211303_P01_WALL-SKIN-SIDE-UPPER-LH_CAD (Autodesk Fusion 360 design; units mm, degrees)
part number: 2026-11-01-23-47-04-714
description: WALL - SKIN - SIDE UPPER - LH | Vách trái - tấm ốp alu trên | P01
part number: 211303
Autodesk Fusion 360 part; units mm, degrees
ref_plane "WorkPlane1" through (0, 0, 1257.26) normal (0, 0, 1) x (1, 0, 0) in component "211303 WALL - SKIN - SIDE UPPER - LH"
sketch "SKETCH - SKIN PLATE" plane through (0, 0, 1257.26) normal (0, 0, 1) x (1, 0, 0) in component "211303 WALL - SKIN - SIDE UPPER - LH"
  line L0 (-1250, -642.74) -> (-1247, -642.74)
  line L1 (-1247, -642.74) -> (-1247, 850)
  line L2 (-1247, 850) -> (-1250, 850)
  line L3 (-1250, 850) -> (-1250, -642.74)
  dimension "d176" = 3
  dimension "d177" = 1492.74
  dimension "d178" = 1250
  dimension "d179" = 642.74
  constraint horizontal L0
  constraint vertical L1
  constraint horizontal L2
  constraint vertical L3
  measures "d176" horizontal distance of L0.start L0.end
  measures "d177" vertical distance of L0.start L2.end
  measures "d178" horizontal distance of origin L0.start
  measures "d179" vertical distance of origin L0.start
extrude "EXTRUDE - SKIN PLATE" add sketch "SKETCH - SKIN PLATE" along normal blind 1142.74 in component "211303 WALL - SKIN - SIDE UPPER - LH"
ref_plane "WorkPlane2" through (0, 0, 1257.26) normal (0, 0, 1) x (1, 0, 0) in component "211303 WALL - SKIN - SIDE UPPER - LH"
sketch "SKETCH - SKIN BACK RETURN" plane through (0, 0, 1257.26) normal (0, 0, 1) x (1, 0, 0) in component "211303 WALL - SKIN - SIDE UPPER - LH"
  line L0 (-1247, 847) -> (-1204, 847)
  line L1 (-1204, 847) -> (-1204, 850)
  line L2 (-1204, 850) -> (-1247, 850)
  line L3 (-1247, 850) -> (-1247, 847)
  dimension "d184" = 43
  dimension "d185" = 3
  dimension "d186" = 1247
  dimension "d187" = 847
  constraint horizontal L0
  constraint vertical L1
  constraint horizontal L2
  constraint vertical L3
  measures "d184" horizontal distance of L0.start L0.end
  measures "d185" vertical distance of L0.start L2.end
  measures "d186" horizontal distance of origin L0.start
  measures "d187" vertical distance of origin L0.start
extrude "JOIN - SKIN BACK RETURN" add sketch "SKETCH - SKIN BACK RETURN" along normal blind 1142.74 in component "211303 WALL - SKIN - SIDE UPPER - LH"
fillet "FILLET - FOLD OUTSIDE RADIUS (MAKER'S GUIDE 4.5)" radius 2 1 edges at (-1250, 850, 1828.63) in component "211303 WALL - SKIN - SIDE UPPER - LH"
component "211303 WALL - SKIN - SIDE UPPER - LH" placed x (1, 0, 0) y (0, 1, 0) z (0, 0, 1) at (0, 0, 0)
equation "pod_w_Ref = 2500 mm" comment "DECIDED: D-01; conventions s4 (X = +-1250)"
equation "pod_d_Ref = 1700 mm" comment "DECIDED: D-01; conventions s4 (Y = +-850)"
equation "pod_h_Ref = 2400 mm" comment "DECIDED: D-21 (room floor to roof skin top)"
equation "glide_h_Ref = 10 mm" comment "ASSUMPTION: layout study inputs.py glide_h"
equation "band_h_Ref = 100 mm" comment "SOURCE: layout study B1 list B-BAND 100x40; inputs.py base_h"
equation "outer_t_Ref = skin_t_Ref + bond_t_Ref + frame_t_Ref" comment "DECIDED: PM ruling 2026-10-31: ACP 3 + bond line 3 + frame 40, walls and ceiling (was 43)"
equation "cav_gap_Ref = 4 mm" comment "DECIDED: D-16, D-42: the gap between the outer panel and the lining cassette in the wall and ceiling stack"
equation "cass_t_Ref = 34 mm" comment "SOURCE: layout study B1 final list L-CASS 34 (tray + 25 gap + felt 9)"
equation "stack_t_Ref = outer_t_Ref + cav_gap_Ref + cass_t_Ref" comment "CALCULATION: D-16, D-42 stack, walls and ceiling: outer panel + cavity gap + cassette (PM ruling 2026-10-31 on outer_t)"
equation "wall_depth_Ref = 1495 mm" comment "DECIDED: PM ruling pass C: side walls start at the decor back plate (Y -645), as v1 (1496)"
equation "lin_gap_Ref = 4 mm" comment "ASSUMPTION: PM ruling pass C: gap above the upper side linings so they stay floating (= the 4 mm stack gap)"
equation "seam_gap_Ref = 2.26 mm" comment "DECIDED: PM ruling 2026-10-31 (Mechanical Checker F-001, F-005): the Joints Engineer's 2.26 mm at all nine site seam types, set by a metal stop (1.5 stop washer + 0.76 rivnut head; joints register section 2.8)"
equation "wall_z0_Ref = glide_h_Ref + band_h_Ref" comment "CALCULATION: base band top: glides + band"
equation "panel_z0_Ref = wall_z0_Ref + seam_gap_Ref" comment "CALCULATION: walls stand one seam_gap above the band top (joints register 2.8, IF-01)"
equation "wall_h_Ref = pod_h_Ref - wall_z0_Ref" comment "CALCULATION: 2290 = layout study v2_model wall_h"
equation "side_h_Ref = ( wall_h_Ref - 2 * seam_gap_Ref ) / 2" comment "CALCULATION: D-23: 2 sheets per side wall; the gap on the band and the horizontal seam (joints register 2.8)"
equation "back_oh_Ref = pod_h_Ref - outer_t_Ref - seam_gap_Ref - panel_z0_Ref" comment "CALCULATION: PM ruling 2026-10-31 (pass D, F-004): the back outer frames run up to the ceiling frame (pod_h - outer_t), less the seam_gap under it, closing the slot at the back top edge"
equation "back_ph_Ref = ( back_oh_Ref - seam_gap_Ref ) / 2" comment "CALCULATION: D-23: 4 sheets on the back, two equal rows with one seam_gap between them (joints register 2.8); the lower back linings match the lower row, as on the side walls"
equation "n_base_bolt_Ref = 4" comment "DECIDED: PM ruling 2026-10-31, J-BASE-01: bolts per panel along the band, evenly spaced"
equation "skin_t_Ref = 3 mm" comment "DECIDED: ACP skin, walls and ceiling (D-16; PM ruling 2026-10-31 on outer_t)"
equation "bond_t_Ref = 3 mm" comment "DECIDED: bond line between the ACP and the frame (PM ruling 2026-10-31 on outer_t)"
equation "frame_t_Ref = 40 mm" comment "DECIDED: aluminium frame tube depth, walls and ceiling (PM ruling 2026-10-31 on outer_t)"
equation "bolt_edge_inset_Ref = 220 mm" comment "DECIDED: PM ruling 2026-10-31: on every bolted edge the end bolts sit this far in from each panel end (the FRAME end, where the bolts go), the rest evenly spaced"
equation "spigot_inset_Ref = 100 mm" comment "DECIDED: PM ruling 2026-10-31: locating spigots this far in from each panel end (round hole at one end, slot at the other)"
equation "ceil_bolt_z_Ref = pod_h_Ref - outer_t_Ref + frame_t_Ref / 2" comment "DECIDED: PM ruling 2026-10-31, J-CEIL-01 wall to ceiling: the bolt line on the ceiling frame's centre (Z 2374)"
equation "pod_w = pod_w_Ref" comment "LINKED: pod_w_Ref, derived from 100000_P04_POD-SKELETON_CAD v6 (skeleton is the single source)"
equation "pod_d = pod_d_Ref" comment "LINKED: pod_d_Ref, derived from 100000_P04_POD-SKELETON_CAD v6 (skeleton is the single source)"
equation "pod_h = pod_h_Ref" comment "LINKED: pod_h_Ref, derived from 100000_P04_POD-SKELETON_CAD v6 (skeleton is the single source)"
equation "wall_depth = wall_depth_Ref" comment "LINKED: wall_depth_Ref, derived from 100000_P04_POD-SKELETON_CAD v6 (skeleton is the single source)"
equation "wall_z0 = wall_z0_Ref" comment "LINKED: wall_z0_Ref, derived from 100000_P04_POD-SKELETON_CAD v6 (skeleton is the single source)"
equation "panel_z0 = panel_z0_Ref" comment "LINKED: panel_z0_Ref, derived from 100000_P04_POD-SKELETON_CAD v6 (skeleton is the single source)"
equation "side_h = side_h_Ref" comment "LINKED: side_h_Ref, derived from 100000_P04_POD-SKELETON_CAD v6 (skeleton is the single source)"
equation "back_ph = back_ph_Ref" comment "LINKED: back_ph_Ref, derived from 100000_P04_POD-SKELETON_CAD v6 (skeleton is the single source)"
equation "stack_t = stack_t_Ref" comment "LINKED: stack_t_Ref, derived from 100000_P04_POD-SKELETON_CAD v6 (skeleton is the single source)"
equation "outer_t = outer_t_Ref" comment "LINKED: outer_t_Ref, derived from 100000_P04_POD-SKELETON_CAD v6 (skeleton is the single source)"
equation "cass_t = cass_t_Ref" comment "LINKED: cass_t_Ref, derived from 100000_P04_POD-SKELETON_CAD v6 (skeleton is the single source)"
equation "lin_gap = lin_gap_Ref" comment "LINKED: lin_gap_Ref, derived from 100000_P04_POD-SKELETON_CAD v6 (skeleton is the single source)"
equation "seam_gap = seam_gap_Ref" comment "LINKED: seam_gap_Ref, derived from 100000_P04_POD-SKELETON_CAD v6 (skeleton is the single source)"
equation "skin_t = skin_t_Ref" comment "LINKED: skin_t_Ref, derived from 100000_P04_POD-SKELETON_CAD v6 (skeleton is the single source)"
equation "bond_t = bond_t_Ref" comment "LINKED: bond_t_Ref, derived from 100000_P04_POD-SKELETON_CAD v6 (skeleton is the single source)"
equation "bolt_edge_inset = bolt_edge_inset_Ref" comment "LINKED: bolt_edge_inset_Ref, derived from 100000_P04_POD-SKELETON_CAD v6 (skeleton is the single source)"
equation "spigot_inset = spigot_inset_Ref" comment "LINKED: spigot_inset_Ref, derived from 100000_P04_POD-SKELETON_CAD v6 (skeleton is the single source)"
equation "n_base_bolt = n_base_bolt_Ref" comment "LINKED: n_base_bolt_Ref, derived from 100000_P04_POD-SKELETON_CAD v6 (skeleton is the single source)"
equation "ceil_bolt_z = ceil_bolt_z_Ref" comment "LINKED: ceil_bolt_z_Ref, derived from 100000_P04_POD-SKELETON_CAD v6 (skeleton is the single source)"
equation "tube_w = 20 mm" comment "CONFIRMED: D-34, D-54, kept by D-131 (the same outside sections in welded, galvanized steel box tube): 20 x 40; the 20 mm face carries the skin, so the 40 mm runs through the wall (outer_t = ACP 3 + frame 40)"
equation "tube_d = outer_t - skin_t - bond_t" comment "CALCULATION: frame depth = outer panel 46 - skin 3 - bond 3 = 40 (D-34)"
equation "tube_t = 1.2 mm" comment "SOURCE: the Joints Engineer's gauges for D-131 (PM ruling, 2026-11-01 05:29): 1.2 for a side panel's rails and front stile, for margin against thin tube and weak welds (corner lift 74% on L1 and L2)"
equation "corner_t = 1.0 mm" comment "SOURCE: the same: the 40 x 40 members (the back stile, and the upper panel's top member) stay 1.0"
equation "stud_t = 0.8 mm" comment "SOURCE: the same: the studs at 0.8 (no rivnut, only the skin's bond line)"
equation "plate_t = 2 mm" comment "SOURCE: the Joints Engineer's corner detail (2026-11-01 05:05): a 2 mm steel plate welded into each mitre, the members cut back so it fits, centred on the old mitre line"
equation "stile_pitch_max = 300 mm" comment "CONFIRMED: PM ruling 2026-11-01 (D-131 sample): the ACP flexes 2 mm or less under a 100 N push at a bay's centre, edges simply supported (make_acp_spans.py), so members about 300 apart; it was 400 (D-16, D-34)"
equation "pnl_len = wall_depth - seam_gap" comment "CALCULATION: D-49 depth 1495 less the 2.26 gap at the decor back plate (PM ruling on F-008): 1492.74"
equation "pnl_h = pod_h - ( panel_z0 + side_h + seam_gap )" comment "CALCULATION: lower: skeleton side_h (2 sheets per side wall, D-23); upper: from one seam gap above the lower row to the roof datum pod_h, as the skeleton's envelope (equal to side_h at P04 values)"
equation "skin_ret = outer_t - skin_t" comment "ASSUMPTION: back return of the side skin: covers the frame's back end at the corner, where the side skin covers the back panel's edge (D-55; sample drawing D04). V-groove and fold per the ACP maker (HOLD H16)"
equation "skin_fold_r = 2 mm" comment "SOURCE: outside radius of the back return's V-grooved fold: over 2 at the fold (the panel maker's guide 01/2021/HDTC-VD 4.5 and figure 4.5: under 2 cracks the face and voids the warranty); modelled (the Lead's ruling, 2026-11-01)"
equation "skin_setback = 0 mm" comment "ASSUMPTION: skin edge set back from the frame's top and bottom edges: 0, so the outside reveal equals the 2.26 seam gap (D-23: crisp, aligned reveals; joints register 2.8 leaves the setback to the WALL drawing)"
equation "frm_len = pnl_len - skin_t - bond_t" comment "CALCULATION: the frame stops one bond line (bond_t) inside the skin's back return, which is bonded to it as the main face is (the Lead's ruling, 2026-11-01: every skin face that meets a frame is bonded at bond_t, no zero fits)"
equation "frm_h = pnl_h" comment "ASSUMPTION: the frame fills the skeleton envelope height; seam and base gasket gaps are set by the joint register (HOLD)"
equation "corner_w = 40 mm" comment "CONFIRMED: the side panel's back member is 40 x 40 x 1.2 (PM ruling on the joints register, item 3, 2026-10-31; register F2, FR-06): the back corner joint needs a 37+ mm overlap for the rivnut and the bolt"
equation "stile_n_mid = 5" comment "CALCULATION: D-131 sample (PM 2026-11-01): 5 studs, placed clear of the bolts (stud_c1 to stud_c5): 4 even studs about 300 apart pass the skin's 2 mm limit but stand 14 and 24 mm from two bolts, under R-J14's 30"
equation "top_h = corner_w" comment "CONFIRMED: top member height: 20 on a lower panel; 40 x 40 on an upper panel, where the ceiling bolts in (PM ruling R-J3, joints register FR-06)"
equation "stile_len = frm_h - tube_w - top_h" comment "CALCULATION: stiles fit between the full-length rails (butt joints)"
equation "ceil_bolt_dz = pod_h - ceil_bolt_z" comment "CALCULATION: J-CEIL-01 side bolts on the ceiling frame tube's centre: the skeleton's ceil_bolt_z, Z 2374 on P04 (joints register R-J15, FR-07)"
equation "fill_t = tube_d" comment "CALCULATION: 40 mm PET fill fills the frame depth (D-34; layout study 40 mm)"
equation "bolt_d = 7 mm" comment "CONFIRMED: PM ruling on F-009: bolt holes 7.0 (0.51 float), position tolerance 0.4 (+-0.2) from the spigot hole, CNC or drill jig (joints register FR-02)"
equation "access_d = 19 mm" comment "CALCULATION: register FR-03: passes the 18 mm head washer (ISO 7093-1, R-J10), the M6 head and the 5 mm key; holds the grommet retainer (H-02)"
equation "bolt_line_y = pod_d / 2 - skin_t - bond_t - tube_d / 2" comment "CONFIRMED: J-WALL-02 bolt line on the back panel's tube centre, Y 824 (joints register R-J15, FR-07)"
equation "rivnut_d = 10 mm" comment "CONFIRMED: D-163 (the Lead's ruling, 2026-11-01): Sherex CAL2-610-4.2 in a round drilled hole Ø10.00 +0.10/0, inside the maker's 10.00 +0.15/-0.0 (Sherex drawing CAL2-610-4.2 rev B, note 2) so the bolt-hole stack ST-03 stays positive; T06's spin-out test confirms it"
equation "spigot_d = 8.5 mm" comment "ASSUMPTION: register FR-05: hole for the 8 mm locating spigot H-05"
equation "pin_slot_w = 8.5 mm" comment "CONFIRMED: D-169 (Joints, 2026-11-01): the decor block's pin slots 8.5 wide in X"
equation "pin_slot_l = 12 mm" comment "CONFIRMED: D-169: 12 long in Z, along the member; on the bolt line, 100 from each end of the seam edge (the register's spigot rule)"
equation "spigot_slot = 16 mm" comment "CONFIRMED: D-167 (the Lead's ruling, 2026-11-01): the seam gasket is 4.78 (PORON 4701-40's standard), so the side panels' back-end slot for the second spigot grows from 8.5 x 14 to 8.5 x 16, ±4 of travel, the panel held 3.4 out"
equation "spigot_edge = spigot_inset" comment "CALCULATION: the skeleton's spigot_inset: spigots 100 from each end of the edge (PM ruling 2026-10-31, R-J13)"
equation "bolt_edge = bolt_edge_inset" comment "CALCULATION: the skeleton's bolt_edge_inset: end bolts 220 in from the panel's ends, evenly spaced, every bolt 30 or more from any stile (PM ruling 2026-10-31, R-J14)"
equation "n_side_jnt = 3" comment "SOURCE: register J-WALL-02, J-FRONT-01: 3 bolts up each side panel"
equation "side_jnt_pitch = ( pnl_h - 2 * bolt_edge ) / ( n_side_jnt - 1 )" comment "CALCULATION: equal pitch of the 3 bolts up the corner and decor joints"
equation "pocket_w = 60 mm" comment "ASSUMPTION: register FR-10: fill left out 60 x 60 next to each bolt for the key"
equation "corner_z0 = panel_z0 + back_ph + seam_gap" comment "CALCULATION: bottom of the back panel row this side panel meets at the corner (B1/B2 or B3/B4, skeleton P04)"
equation "corner_bolt_pitch = ( back_ph - 2 * bolt_edge ) / ( n_side_jnt - 1 )" comment "CALCULATION: J-WALL-02 bolts run along the back panel's edge: 220, 559.31, 898.61 on its 1118.61 (joints register 2.9)"
equation "n_len_bolt = n_base_bolt" comment "CALCULATION: the skeleton's n_base_bolt (4): the same count on J-WALL-01 and the J-CEIL-01 side edges (register 2.9)"
equation "ceil_bolt_pitch = ( wall_depth - 2 * bolt_edge ) / ( n_len_bolt - 1 )" comment "CALCULATION: J-CEIL-01 side edge: 4 bolts along the ceiling's 1495 from Y -645 (its front edge), 220 rule, pitch 351.67 on P04; CEILING drills the same (PM ruling 2026-10-31 16:55; joints register 2.9)"
equation "len_bolt_pitch = ( pnl_len - 2 * bolt_edge ) / ( n_len_bolt - 1 )" comment "CALCULATION: even pitch of the bolts along the panel"
equation "stud_c1 = bolt_edge + 50 mm" comment "CALCULATION: 50 past the 1st bolt: its face 40 clear of it (R-J14)"
equation "stud_c2 = bolt_edge + len_bolt_pitch - 50 mm" comment "CALCULATION: 50 before the 2nd bolt (R-J14)"
equation "stud_c3 = bolt_edge + 1.5 * len_bolt_pitch" comment "CALCULATION: midway between the 2nd and 3rd bolts"
equation "stud_c4 = bolt_edge + 2 * len_bolt_pitch + 50 mm" comment "CALCULATION: 50 past the 3rd bolt (R-J14)"
equation "stud_c5 = bolt_edge + 3 * len_bolt_pitch - 50 mm" comment "CALCULATION: 50 before the 4th bolt (R-J14)"
equation "felt_t = 9 mm" comment "SOURCE: plan VT03-PET 9 mm PET felt; HW-SEL A3; D-31 (the factory's felt)"
equation "tray_t = 0.5 mm" comment "CONFIRMED: D-37: galvanised steel tray 0.5 mm"
equation "tray_h = cass_t" comment "CONFIRMED: PM ruling 2026-10-31 (WALL group, option 1): the wall cassettes use the ceiling's tray, returns the full cassette depth (34) turned in as lips that hold the felt, no ribs; settles H09 for the walls"
equation "lip_w = 12 mm" comment "CONFIRMED: PM ruling 2026-10-31 (WALL group, option 1): 12 mm lips hold the felt edge"
equation "bend_r = tray_t" comment "ASSUMPTION: inside bend radius 1 x t for 0.5 mm DX51D (the sheet metal rule's bend radius is its Thickness); the factory's tooling sets it (guideline 9)"
equation "felt_c = 1 mm" comment "ASSUMPTION: felt edge clearance inside the returns, as the ceiling cassette"
equation "gap_h = tray_h - felt_t - 2 * tray_t" comment "CALCULATION: air gap between the tray base and the felt (24): the acoustic gap (D-17) and the cable path (D-26)"
equation "lin_front_dy = 0 mm" comment "CONFIRMED: the left-hand cassettes start at the decor back plate (D-57); the right-hand ones 5 mm behind it, clear of DR's inner panel (Lead ruling 2026-11-01)"
equation "cass_len = wall_depth - stack_t + cass_t - lin_front_dy" comment "CALCULATION: from the cassette's front end (lin_front_dy behind the decor back plate) to past the back cassette's face, closing the inside corner (D-57): 1445 on the left, 1440 on the right"
equation "cass_h = pod_h - outer_t - lin_gap - ( panel_z0 + side_h + seam_gap )" comment "CALCULATION: lower: the panel height; upper: stops lin_gap under the roof frame so it floats (D-57)"
equation "clip_zone_h = 60 mm" comment "ASSUMPTION: height of each reserved clip zone (H03: no clip named)"
equation "clip_zone_dz = 100 mm" comment "ASSUMPTION: clip zone centre from the cassette's top and bottom edges (H03)"
equation "stopw_od = 20 mm" comment "SOURCE: joints register H-08: stop washer Ø10.5 x Ø20 x 1.5 (PROPOSED part)"
equation "stopw_id = 10.5 mm" comment "SOURCE: joints register H-08"
equation "stopw_t = 1.5 mm" comment "SOURCE: joints register H-08: rivnut head 0.76 + washer 1.5 = the 2.26 stop (R-J5)"
equation "rivnut_head_d = 12.95 mm" comment "SOURCE: Sherex CAL2-610-4.2 rev B: flange Ø12.45 to 12.95, the largest modelled (D-163)"
equation "rivnut_head_t = 0.76 mm" comment "SOURCE: Sherex CAL2-610-4.2 rev B: flange 0.68 to 0.84, its middle; with the 1.5 stop washer the 2.26 stop (R-J5), as before (D-163)"
equation "rivnut_body_d = 9.91 mm" comment "SOURCE: Sherex CAL2-610-4.2 rev B: knurled body Ø9.91 max (D-163)"
equation "rivnut_len = 9.65 mm" comment "SOURCE: Sherex CAL2-610-4.2 rev B, note 3: installed length 9.65 max under the flange (14.35 to 15.11 before setting); the bulge inside the tube is not modelled (D-163)"
equation "m6_d = 6 mm" comment "CALCULATION: M6 threads shown at their 6 mm major diameter (no modelled thread)"
equation "spigot_pin_d = 8 mm" comment "SOURCE: joints register H-05: Ø8 stainless pin; the part itself is Joints' 831001 STEP, placed as it is (F-189)"
equation "spigot_proud = 8 mm" comment "SOURCE: joints register H-05 and Joints' README: the pin's top 8.00 above the tube face (Z 7.24 above its origin on the rivnut head)"
equation "d174 = ( panel_z0 + side_h + seam_gap ) + skin_setback"
equation "d176 = ( -( pod_w / 2 - skin_t ) ) - ( -( pod_w / 2 ) )"
equation "d177 = ( pod_d / 2 ) - ( pod_d / 2 - wall_depth + seam_gap )"
equation "d178 = abs(-( pod_w / 2 ))"
equation "d179 = abs(pod_d / 2 - wall_depth + seam_gap)"
equation "d180 = ( pod_h ) - ( ( panel_z0 + side_h + seam_gap ) + skin_setback )"
equation "d182 = ( panel_z0 + side_h + seam_gap ) + skin_setback"
equation "d184 = ( -( pod_w / 2 - skin_t - skin_ret ) ) - ( -( pod_w / 2 - skin_t ) )"
equation "d185 = ( pod_d / 2 ) - ( pod_d / 2 - skin_t )"
equation "d186 = abs(-( pod_w / 2 - skin_t ))"
equation "d187 = abs(pod_d / 2 - skin_t)"
equation "d188 = ( pod_h ) - ( ( panel_z0 + side_h + seam_gap ) + skin_setback )"
equation "d191 = skin_fold_r"
named bodies: "SKIN - ACP 3 WITH BACK RETURN"
